211601_P01_WALL-CAVITY-FILL-BACK-LOWER-B1_CAD (Autodesk Fusion 360 design; units mm, degrees)
description: WALL - CAVITY FILL - BACK LOWER - B1 | Vách hậu - bông PET dưới trái | P01 | position B1
part number: 211601
description: WALL - CAVITY FILL - BACK LOWER - B1 | Vách hậu - bông PET dưới trái | P01
Autodesk Fusion 360 part; units mm, degrees
ref_plane "WorkPlane1" through (0, 0, 132.26) normal (0, 0, 1) x (1, 0, 0) in component "211601 WALL - CAVITY FILL - BACK LOWER - B1"
sketch "SKETCH - FILL BAY 1" plane through (0, 0, 132.26) normal (0, 0, 1) x (1, 0, 0) in component "211601 WALL - CAVITY FILL - BACK LOWER - B1"
  line L0 (-1181.74, 804) -> (-808.7433, 804)
  line L1 (-808.7433, 804) -> (-808.7433, 844)
  line L2 (-808.7433, 844) -> (-1181.74, 844)
  line L3 (-1181.74, 844) -> (-1181.74, 804)
  dimension "d162" = 372.9967
  dimension "d163" = 40
  dimension "d164" = 1181.74
  dimension "d165" = 804
  constraint horizontal L0
  constraint vertical L1
  constraint horizontal L2
  constraint vertical L3
  measures "d162" horizontal distance of L0.start L0.end
  measures "d163" vertical distance of L0.start L2.end
  measures "d164" horizontal distance of origin L0.start
  measures "d165" vertical distance of origin L0.start
extrude "EXTRUDE - FILL BAY 1" add sketch "SKETCH - FILL BAY 1" along normal blind 1078.61 makes body 1 in component "211601 WALL - CAVITY FILL - BACK LOWER - B1"
pattern_linear "PATTERN - FILL BAYS" count 3 spacing 392.9967 along (1, 0, 0) of bodies 1 makes body 2 at (-540.0789, 844, 851.3333) makes body 3 at (-147.0822, 844, 491.7967) in component "211601 WALL - CAVITY FILL - BACK LOWER - B1"
ref_plane "WorkPlane2" through (0, 0, 132.26) normal (0, 0, 1) x (1, 0, 0) in component "211601 WALL - CAVITY FILL - BACK LOWER - B1"
sketch "SKETCH - FILL POCKET BOTTOM BOLT 1" plane through (0, 0, 132.26) normal (0, 0, 1) x (1, 0, 0) in component "211601 WALL - CAVITY FILL - BACK LOWER - B1"
  line L0 (-1011.74, 804) -> (-951.74, 804)
  line L1 (-951.74, 804) -> (-951.74, 844)
  line L2 (-951.74, 844) -> (-1011.74, 844)
  line L3 (-1011.74, 844) -> (-1011.74, 804)
  dimension "d174" = 60
  dimension "d175" = 40
  dimension "d176" = 1011.74
  dimension "d177" = 804
  constraint horizontal L0
  constraint vertical L1
  constraint horizontal L2
  constraint vertical L3
  measures "d174" horizontal distance of L0.start L0.end
  measures "d175" vertical distance of L0.start L2.end
  measures "d176" horizontal distance of origin L0.start
  measures "d177" vertical distance of origin L0.start
extrude "CUT - FILL POCKET BOTTOM BOLT 1" cut sketch "SKETCH - FILL POCKET BOTTOM BOLT 1" along normal blind 60 bodies 1 in component "211601 WALL - CAVITY FILL - BACK LOWER - B1"
ref_plane "WorkPlane3" through (0, 0, 132.26) normal (0, 0, 1) x (1, 0, 0) in component "211601 WALL - CAVITY FILL - BACK LOWER - B1"
sketch "SKETCH - FILL POCKET BOTTOM BOLT 2" plane through (0, 0, 132.26) normal (0, 0, 1) x (1, 0, 0) in component "211601 WALL - CAVITY FILL - BACK LOWER - B1"
  line L0 (-758.7433, 804) -> (-698.7433, 804)
  line L1 (-698.7433, 804) -> (-698.7433, 844)
  line L2 (-698.7433, 844) -> (-758.7433, 844)
  line L3 (-758.7433, 844) -> (-758.7433, 804)
  dimension "d182" = 60
  dimension "d183" = 40
  dimension "d184" = 758.7433
  dimension "d185" = 804
  constraint horizontal L0
  constraint vertical L1
  constraint horizontal L2
  constraint vertical L3
  measures "d182" horizontal distance of L0.start L0.end
  measures "d183" vertical distance of L0.start L2.end
  measures "d184" horizontal distance of origin L0.start
  measures "d185" vertical distance of origin L0.start
extrude "CUT - FILL POCKET BOTTOM BOLT 2" cut sketch "SKETCH - FILL POCKET BOTTOM BOLT 2" along normal blind 60 bodies 2 in component "211601 WALL - CAVITY FILL - BACK LOWER - B1"
ref_plane "WorkPlane4" through (0, 0, 132.26) normal (0, 0, 1) x (1, 0, 0) in component "211601 WALL - CAVITY FILL - BACK LOWER - B1"
sketch "SKETCH - FILL POCKET BOTTOM BOLT 3" plane through (0, 0, 132.26) normal (0, 0, 1) x (1, 0, 0) in component "211601 WALL - CAVITY FILL - BACK LOWER - B1"
  line L0 (-505.7467, 804) -> (-445.7467, 804)
  line L1 (-445.7467, 804) -> (-445.7467, 844)
  line L2 (-445.7467, 844) -> (-505.7467, 844)
  line L3 (-505.7467, 844) -> (-505.7467, 804)
  dimension "d190" = 60
  dimension "d191" = 40
  dimension "d192" = 505.7467
  dimension "d193" = 804
  constraint horizontal L0
  constraint vertical L1
  constraint horizontal L2
  constraint vertical L3
  measures "d190" horizontal distance of L0.start L0.end
  measures "d191" vertical distance of L0.start L2.end
  measures "d192" horizontal distance of origin L0.start
  measures "d193" vertical distance of origin L0.start
extrude "CUT - FILL POCKET BOTTOM BOLT 3" cut sketch "SKETCH - FILL POCKET BOTTOM BOLT 3" along normal blind 60 bodies 2 in component "211601 WALL - CAVITY FILL - BACK LOWER - B1"
ref_plane "WorkPlane5" through (0, 0, 132.26) normal (0, 0, 1) x (1, 0, 0) in component "211601 WALL - CAVITY FILL - BACK LOWER - B1"
sketch "SKETCH - FILL POCKET BOTTOM BOLT 4" plane through (0, 0, 132.26) normal (0, 0, 1) x (1, 0, 0) in component "211601 WALL - CAVITY FILL - BACK LOWER - B1"
  line L0 (-252.75, 804) -> (-192.75, 804)
  line L1 (-192.75, 804) -> (-192.75, 844)
  line L2 (-192.75, 844) -> (-252.75, 844)
  line L3 (-252.75, 844) -> (-252.75, 804)
  dimension "d198" = 60
  dimension "d199" = 40
  dimension "d200" = 252.75
  dimension "d201" = 804
  constraint horizontal L0
  constraint vertical L1
  constraint horizontal L2
  constraint vertical L3
  measures "d198" horizontal distance of L0.start L0.end
  measures "d199" vertical distance of L0.start L2.end
  measures "d200" horizontal distance of origin L0.start
  measures "d201" vertical distance of origin L0.start
extrude "CUT - FILL POCKET BOTTOM BOLT 4" cut sketch "SKETCH - FILL POCKET BOTTOM BOLT 4" along normal blind 60 bodies 3 in component "211601 WALL - CAVITY FILL - BACK LOWER - B1"
ref_plane "WorkPlane6" through (0, 0, 302.26) normal (0, 0, 1) x (1, 0, 0) in component "211601 WALL - CAVITY FILL - BACK LOWER - B1"
sketch "SKETCH - FILL POCKET CORNER BOLT 1" plane through (0, 0, 302.26) normal (0, 0, 1) x (1, 0, 0) in component "211601 WALL - CAVITY FILL - BACK LOWER - B1"
  line L0 (-1181.74, 804) -> (-1121.74, 804)
  line L1 (-1121.74, 804) -> (-1121.74, 844)
  line L2 (-1121.74, 844) -> (-1181.74, 844)
  line L3 (-1181.74, 844) -> (-1181.74, 804)
  dimension "d206" = 60
  dimension "d207" = 40
  dimension "d208" = 1181.74
  dimension "d209" = 804
  constraint horizontal L0
  constraint vertical L1
  constraint horizontal L2
  constraint vertical L3
  measures "d206" horizontal distance of L0.start L0.end
  measures "d207" vertical distance of L0.start L2.end
  measures "d208" horizontal distance of origin L0.start
  measures "d209" vertical distance of origin L0.start
extrude "CUT - FILL POCKET CORNER BOLT 1" cut sketch "SKETCH - FILL POCKET CORNER BOLT 1" along normal blind 60 bodies 1 in component "211601 WALL - CAVITY FILL - BACK LOWER - B1"
ref_plane "WorkPlane7" through (0, 0, 641.565) normal (0, 0, 1) x (1, 0, 0) in component "211601 WALL - CAVITY FILL - BACK LOWER - B1"
sketch "SKETCH - FILL POCKET CORNER BOLT 2" plane through (0, 0, 641.565) normal (0, 0, 1) x (1, 0, 0) in component "211601 WALL - CAVITY FILL - BACK LOWER - B1"
  line L0 (-1181.74, 804) -> (-1121.74, 804)
  line L1 (-1121.74, 804) -> (-1121.74, 844)
  line L2 (-1121.74, 844) -> (-1181.74, 844)
  line L3 (-1181.74, 844) -> (-1181.74, 804)
  dimension "d214" = 60
  dimension "d215" = 40
  dimension "d216" = 1181.74
  dimension "d217" = 804
  constraint horizontal L0
  constraint vertical L1
  constraint horizontal L2
  constraint vertical L3
  measures "d214" horizontal distance of L0.start L0.end
  measures "d215" vertical distance of L0.start L2.end
  measures "d216" horizontal distance of origin L0.start
  measures "d217" vertical distance of origin L0.start
extrude "CUT - FILL POCKET CORNER BOLT 2" cut sketch "SKETCH - FILL POCKET CORNER BOLT 2" along normal blind 60 bodies 1 in component "211601 WALL - CAVITY FILL - BACK LOWER - B1"
ref_plane "WorkPlane8" through (0, 0, 980.87) normal (0, 0, 1) x (1, 0, 0) in component "211601 WALL - CAVITY FILL - BACK LOWER - B1"
sketch "SKETCH - FILL POCKET CORNER BOLT 3" plane through (0, 0, 980.87) normal (0, 0, 1) x (1, 0, 0) in component "211601 WALL - CAVITY FILL - BACK LOWER - B1"
  line L0 (-1181.74, 804) -> (-1121.74, 804)
  line L1 (-1121.74, 804) -> (-1121.74, 844)
  line L2 (-1121.74, 844) -> (-1181.74, 844)
  line L3 (-1181.74, 844) -> (-1181.74, 804)
  dimension "d222" = 60
  dimension "d223" = 40
  dimension "d224" = 1181.74
  dimension "d225" = 804
  constraint horizontal L0
  constraint vertical L1
  constraint horizontal L2
  constraint vertical L3
  measures "d222" horizontal distance of L0.start L0.end
  measures "d223" vertical distance of L0.start L2.end
  measures "d224" horizontal distance of origin L0.start
  measures "d225" vertical distance of origin L0.start
extrude "CUT - FILL POCKET CORNER BOLT 3" cut sketch "SKETCH - FILL POCKET CORNER BOLT 3" along normal blind 60 bodies 1 in component "211601 WALL - CAVITY FILL - BACK LOWER - B1"
component "211601 WALL - CAVITY FILL - BACK LOWER - B1" placed x (1, 0, 0) y (0, 1, 0) z (0, 0, 1) at (0, 0, 0)
equation "pod_w_Ref = 2500 mm" comment "DECIDED: D-01; conventions s4 (X = +-1250)"
equation "pod_d_Ref = 1700 mm" comment "DECIDED: D-01; conventions s4 (Y = +-850)"
equation "pod_h_Ref = 2400 mm" comment "DECIDED: D-21 (room floor to roof skin top)"
equation "glide_h_Ref = 10 mm" comment "ASSUMPTION: layout study inputs.py glide_h"
equation "band_h_Ref = 100 mm" comment "SOURCE: layout study B1 list B-BAND 100x40; inputs.py base_h"
equation "outer_t_Ref = skin_t_Ref + bond_t_Ref + frame_t_Ref" comment "DECIDED: PM ruling 2026-10-31: ACP 3 + bond line 3 + frame 40, walls and ceiling (was 43)"
equation "cav_gap_Ref = 4 mm" comment "DECIDED: D-16, D-42: the gap between the outer panel and the lining cassette in the wall and ceiling stack"
equation "cass_t_Ref = 34 mm" comment "SOURCE: layout study B1 final list L-CASS 34 (tray + 25 gap + felt 9)"
equation "stack_t_Ref = outer_t_Ref + cav_gap_Ref + cass_t_Ref" comment "CALCULATION: D-16, D-42 stack, walls and ceiling: outer panel + cavity gap + cassette (PM ruling 2026-10-31 on outer_t)"
equation "lin_gap_Ref = 4 mm" comment "ASSUMPTION: PM ruling pass C: gap above the upper side linings so they stay floating (= the 4 mm stack gap)"
equation "seam_gap_Ref = 2.26 mm" comment "DECIDED: PM ruling 2026-10-31 (Mechanical Checker F-001, F-005): the Joints Engineer's 2.26 mm at all nine site seam types, set by a metal stop (1.5 stop washer + 0.76 rivnut head; joints register section 2.8)"
equation "wall_z0_Ref = glide_h_Ref + band_h_Ref" comment "CALCULATION: base band top: glides + band"
equation "panel_z0_Ref = wall_z0_Ref + seam_gap_Ref" comment "CALCULATION: walls stand one seam_gap above the band top (joints register 2.8, IF-01)"
equation "back_oh_Ref = pod_h_Ref - outer_t_Ref - seam_gap_Ref - panel_z0_Ref" comment "CALCULATION: PM ruling 2026-10-31 (pass D, F-004): the back outer frames run up to the ceiling frame (pod_h - outer_t), less the seam_gap under it, closing the slot at the back top edge"
equation "back_ph_Ref = ( back_oh_Ref - seam_gap_Ref ) / 2" comment "CALCULATION: D-23: 4 sheets on the back, two equal rows with one seam_gap between them (joints register 2.8); the lower back linings match the lower row, as on the side walls"
equation "half_pw_Ref = ( pod_w_Ref - 2 * outer_t_Ref - 3 * seam_gap_Ref ) / 2" comment "CALCULATION: SKIN width of each back and ceiling panel: two skins and three seam_gap seams between the side frames (F-001, joints register 2.8)"
equation "n_base_bolt_Ref = 4" comment "DECIDED: PM ruling 2026-10-31, J-BASE-01: bolts per panel along the band, evenly spaced"
equation "skin_t_Ref = 3 mm" comment "DECIDED: ACP skin, walls and ceiling (D-16; PM ruling 2026-10-31 on outer_t)"
equation "bond_t_Ref = 3 mm" comment "DECIDED: bond line between the ACP and the frame (PM ruling 2026-10-31 on outer_t)"
equation "frame_t_Ref = 40 mm" comment "DECIDED: aluminium frame tube depth, walls and ceiling (PM ruling 2026-10-31 on outer_t)"
equation "close_gap_Ref = 5.5 mm" comment "DECIDED: PM ruling 2026-10-31 (joints register, F-011/F-012): frame gap at the closing seams B1-B2, B3-B4 and C1-C2, which have no hard stop (slotted holes, thicker gasket)"
equation "half_fw_Ref = ( pod_w_Ref - 2 * outer_t_Ref - 2 * seam_gap_Ref - close_gap_Ref ) / 2" comment "CALCULATION: FRAME width of each back and ceiling panel: the skins overhang their frames by half_pw - half_fw at the closing seam (PM ruling 2026-10-31)"
equation "bolt_edge_inset_Ref = 220 mm" comment "DECIDED: PM ruling 2026-10-31: on every bolted edge the end bolts sit this far in from each panel end (the FRAME end, where the bolts go), the rest evenly spaced"
equation "spigot_inset_Ref = 100 mm" comment "DECIDED: PM ruling 2026-10-31: locating spigots this far in from each panel end (round hole at one end, slot at the other)"
equation "pod_w = pod_w_Ref" comment "LINKED: pod_w_Ref, derived from 100000_P04_POD-SKELETON_CAD v4 (skeleton is the single source)"
equation "pod_d = pod_d_Ref" comment "LINKED: pod_d_Ref, derived from 100000_P04_POD-SKELETON_CAD v4 (skeleton is the single source)"
equation "pod_h = pod_h_Ref" comment "LINKED: pod_h_Ref, derived from 100000_P04_POD-SKELETON_CAD v4 (skeleton is the single source)"
equation "panel_z0 = panel_z0_Ref" comment "LINKED: panel_z0_Ref, derived from 100000_P04_POD-SKELETON_CAD v4 (skeleton is the single source)"
equation "back_ph = back_ph_Ref" comment "LINKED: back_ph_Ref, derived from 100000_P04_POD-SKELETON_CAD v4 (skeleton is the single source)"
equation "back_oh = back_oh_Ref" comment "LINKED: back_oh_Ref, derived from 100000_P04_POD-SKELETON_CAD v4 (skeleton is the single source)"
equation "half_pw = half_pw_Ref" comment "LINKED: half_pw_Ref, derived from 100000_P04_POD-SKELETON_CAD v4 (skeleton is the single source)"
equation "half_fw = half_fw_Ref" comment "LINKED: half_fw_Ref, derived from 100000_P04_POD-SKELETON_CAD v4 (skeleton is the single source)"
equation "close_gap = close_gap_Ref" comment "LINKED: close_gap_Ref, derived from 100000_P04_POD-SKELETON_CAD v4 (skeleton is the single source)"
equation "stack_t = stack_t_Ref" comment "LINKED: stack_t_Ref, derived from 100000_P04_POD-SKELETON_CAD v4 (skeleton is the single source)"
equation "outer_t = outer_t_Ref" comment "LINKED: outer_t_Ref, derived from 100000_P04_POD-SKELETON_CAD v4 (skeleton is the single source)"
equation "cass_t = cass_t_Ref" comment "LINKED: cass_t_Ref, derived from 100000_P04_POD-SKELETON_CAD v4 (skeleton is the single source)"
equation "lin_gap = lin_gap_Ref" comment "LINKED: lin_gap_Ref, derived from 100000_P04_POD-SKELETON_CAD v4 (skeleton is the single source)"
equation "seam_gap = seam_gap_Ref" comment "LINKED: seam_gap_Ref, derived from 100000_P04_POD-SKELETON_CAD v4 (skeleton is the single source)"
equation "skin_t = skin_t_Ref" comment "LINKED: skin_t_Ref, derived from 100000_P04_POD-SKELETON_CAD v4 (skeleton is the single source)"
equation "bond_t = bond_t_Ref" comment "LINKED: bond_t_Ref, derived from 100000_P04_POD-SKELETON_CAD v4 (skeleton is the single source)"
equation "bolt_edge_inset = bolt_edge_inset_Ref" comment "LINKED: bolt_edge_inset_Ref, derived from 100000_P04_POD-SKELETON_CAD v4 (skeleton is the single source)"
equation "spigot_inset = spigot_inset_Ref" comment "LINKED: spigot_inset_Ref, derived from 100000_P04_POD-SKELETON_CAD v4 (skeleton is the single source)"
equation "n_base_bolt = n_base_bolt_Ref" comment "LINKED: n_base_bolt_Ref, derived from 100000_P04_POD-SKELETON_CAD v4 (skeleton is the single source)"
equation "tube_w = 20 mm" comment "CONFIRMED: D-34, D-54: aluminium tube 20 x 40 x 1.2; the 20 mm face carries the skin, so the 40 mm runs through the wall (outer_t = ACP 3 + frame 40). The joint register may turn it for the bond width (HOLD)"
equation "tube_d = outer_t - skin_t - bond_t" comment "CALCULATION: frame depth = outer panel 46 - skin 3 - bond 3 = 40 (D-34)"
equation "tube_t = 1.2 mm" comment "CONFIRMED: D-34, D-54, D-85: perimeter members (rails, front and back stiles) keep the 1.2 mm wall; they carry the rivnuts (grip check passed)"
equation "stud_t = 1.0 mm" comment "CONFIRMED: D-85 (weight): intermediate studs at a 1.0 mm wall; they carry no rivnut, only the skin's bond line"
equation "stile_pitch_max = 400 mm" comment "CONFIRMED: D-16, D-34: members 400 mm apart or less, to keep the ACP flat"
equation "skin_setback = 0 mm" comment "ASSUMPTION: skin edge set back from the frame's top and bottom edges: 0, so the outside reveal equals the 2.26 seam gap (D-23: crisp, aligned reveals; joints register 2.8 leaves the setback to the WALL drawing)"
equation "fill_t = tube_d" comment "CALCULATION: 40 mm PET fill fills the frame depth (D-34; layout study 40 mm)"
equation "bolt_d = 7 mm" comment "CONFIRMED: PM ruling on F-009: bolt holes 7.0 (0.51 float), position tolerance 0.4 (+-0.2) from the spigot hole, CNC or drill jig (joints register FR-02)"
equation "access_d = 19 mm" comment "CALCULATION: register FR-03: passes the 18 mm head washer (ISO 7093-1, R-J10), the M6 head and the 5 mm key; holds the grommet retainer (H-02)"
equation "bolt_line_y = pod_d / 2 - skin_t - bond_t - tube_d / 2" comment "CONFIRMED: J-WALL-02 bolt line on the back panel's tube centre, Y 824 (joints register R-J15, FR-07)"
equation "rivnut_d = 9.53 mm" comment "SOURCE: Sherex CAH3-610-4.2 hole 9.53 +0.10 (HW-SEL A5; register H-03)"
equation "spigot_d = 8.5 mm" comment "ASSUMPTION: register FR-05: hole for the 8 mm locating spigot H-05"
equation "spigot_slot = 14 mm" comment "ASSUMPTION: register FR-05: slot length for the second spigot"
equation "spigot_edge = spigot_inset" comment "CALCULATION: the skeleton's spigot_inset: spigots 100 from each end of the edge (PM ruling 2026-10-31, R-J13)"
equation "bolt_edge = bolt_edge_inset" comment "CALCULATION: the skeleton's bolt_edge_inset: end bolts 220 in from the panel's ends, evenly spaced, every bolt 30 or more from any stile (PM ruling 2026-10-31, R-J14)"
equation "pocket_w = 60 mm" comment "ASSUMPTION: register FR-10: fill left out 60 x 60 next to each bolt for the key"
equation "felt_t = 9 mm" comment "SOURCE: plan VT03-PET 9 mm PET felt; HW-SEL A3; D-31 (the factory's felt)"
equation "tray_t = 0.5 mm" comment "CONFIRMED: D-37: galvanised steel tray 0.5 mm"
equation "tray_h = cass_t" comment "CONFIRMED: PM ruling 2026-10-31 (WALL group, option 1): the wall cassettes use the ceiling's tray, returns the full cassette depth (34) turned in as lips that hold the felt, no ribs; settles H09 for the walls"
equation "lip_w = 12 mm" comment "CONFIRMED: PM ruling 2026-10-31 (WALL group, option 1): 12 mm lips hold the felt edge"
equation "bend_r = tray_t" comment "ASSUMPTION: inside bend radius 1 x t for 0.5 mm DX51D (the sheet metal rule's bend radius is its Thickness); the factory's tooling sets it (guideline 9)"
equation "felt_c = 1 mm" comment "ASSUMPTION: felt edge clearance inside the returns, as the ceiling cassette"
equation "gap_h = tray_h - felt_t - 2 * tray_t" comment "CALCULATION: air gap between the tray base and the felt (24): the acoustic gap (D-17) and the cable path (D-26)"
equation "clip_zone_h = 60 mm" comment "ASSUMPTION: height of each reserved clip zone (H03: no clip named)"
equation "clip_zone_dz = 100 mm" comment "ASSUMPTION: clip zone centre from the cassette's top and bottom edges (H03)"
equation "stopw_od = 20 mm" comment "SOURCE: joints register H-08: stop washer Ø10.5 x Ø20 x 1.5 (PROPOSED part)"
equation "stopw_id = 10.5 mm" comment "SOURCE: joints register H-08"
equation "stopw_t = 1.5 mm" comment "SOURCE: joints register H-08: rivnut head 0.76 + washer 1.5 = the 2.26 stop (R-J5)"
equation "rivnut_head_d = 12.96 mm" comment "SOURCE: Sherex CAH3-610-4.2 head Ø12.96 (joints register H-03, SHX)"
equation "rivnut_head_t = 0.76 mm" comment "SOURCE: Sherex CAH3-610-4.2 head 0.76 ±0.08 (H-03, SHX)"
equation "rivnut_body_d = 9.5 mm" comment "SOURCE: Sherex CAH3-610-4.2 body Ø9.50 max (H-03, SHX)"
equation "rivnut_len = 10.16 mm" comment "SOURCE: Sherex CAH3-610-4.2 installed length 10.16 max under the head (H-03, SHX); the bulge inside the tube is not modelled"
equation "m6_d = 6 mm" comment "CALCULATION: M6 threads shown at their 6 mm major diameter (no modelled thread)"
equation "spigot_pin_d = 8 mm" comment "SOURCE: joints register H-05: Ø8 stainless pin (PROPOSED, assumption sizes)"
equation "spigot_proud = 8 mm" comment "SOURCE: joints register H-05: stands 8 proud (read as: of the joint face)"
equation "spigot_thread_l = 10 mm" comment "ASSUMPTION: M6 thread into the spigot rivnut; H-05 gives no length; 10 stays inside the rivnut's 10.16"
equation "lead_in = 1 mm" comment "SOURCE: joints register 2.10 (R-J9): 1 x 45 degree lead-in on the top edge of each closing-seam face, so the panel beside it drops in past it without catching the bulb seal"
equation "pnl_len = half_pw" comment "CALCULATION: skeleton half_pw: the back panel's skin width (1200.61 on P04)"
equation "frm_len = half_fw" comment "CALCULATION: the skeleton's half_fw, 1198.99: the frame stops close_gap / 2 from X 0 and 1.62 short of its skin (R-J16)"
equation "pnl_h = back_ph" comment "CALCULATION: skeleton back row height (1118.61 on P04)"
equation "frm_h = pnl_h" comment "CALCULATION: the frame fills the row height; the seam gaps are outside it (P04)"
equation "top_h = tube_w" comment "CALCULATION: the back panels' top rails stay 20 x 40 (the ceiling's back member is the 40 x 40, R-J3)"
equation "stile_n_mid = ceil(( frm_len - tube_w ) / stile_pitch_max) - 1" comment "CALCULATION: intermediate stiles so that no stile pitch exceeds stile_pitch_max"
equation "stile_pitch = ( frm_len - tube_w ) / ( stile_n_mid + 1 )" comment "CALCULATION: equal stile pitch, centre to centre"
equation "stile_len = frm_h - 2 * tube_w" comment "CALCULATION: stiles between the full-width rails (butt joints)"
equation "n_len_bolt = n_base_bolt" comment "CALCULATION: the skeleton's n_base_bolt (4): also on the horizontal seam and the ceiling back edge (register 2.9; the skeleton's n_ceil_back_bolt 3 is an old assumption, flagged)"
equation "len_bolt_pitch = ( frm_len - 2 * bolt_edge ) / ( n_len_bolt - 1 )" comment "CALCULATION: 253.00 on P04: 220, 473.00, 725.99, 978.99 from the frame's ends (register 2.9; the skeleton's back_base_pitch uses the 1200.61 skin and gives 253.54, flagged to its owner)"
equation "n_side_jnt = 3" comment "SOURCE: 3 bolts on the back corner and on the closing seam (register 2.9)"
equation "side_jnt_pitch = ( pnl_h - 2 * bolt_edge ) / ( n_side_jnt - 1 )" comment "CALCULATION: 339.31 on P04: 220, 559.31, 898.61 up the 1118.61 edge (register 2.9)"
equation "cass_len = pod_w / 2 - stack_t - seam_gap / 2" comment "ASSUMPTION: PROPOSED (WALL): from the side lining's face to seam_gap / 2 short of X 0. Each cassette hangs on its own panel's frame and the closing seam moves (5.2 to 5.8, register 2.11), so the skeleton's touching edges at X 0 could clash; a 2.26 gap matches the skin seam above it (R-J16) and takes the H-14 edge seal"
equation "cass_h = pnl_h" comment "CALCULATION: lower: the row height; upper: up to lin_gap under the ceiling frame, floating (D-57; P04)"
equation "d160 = ( panel_z0 ) + tube_w"
equation "d162 = ( ( -close_gap / 2 - half_fw ) + stile_pitch ) - ( ( -close_gap / 2 - half_fw ) + tube_w )"
equation "d163 = ( pod_d / 2 - skin_t - bond_t ) - ( pod_d / 2 - outer_t )"
equation "d164 = abs(( -close_gap / 2 - half_fw ) + tube_w)"
equation "d165 = abs(pod_d / 2 - outer_t)"
equation "d166 = ( ( panel_z0 + back_ph ) - top_h ) - ( ( panel_z0 ) + tube_w )"
equation "d168 = stile_n_mid + 1"
equation "d170 = stile_pitch"
equation "d172 = ( panel_z0 ) + tube_w"
equation "d174 = ( ( ( -close_gap / 2 - half_fw ) + bolt_edge + 0 * len_bolt_pitch ) + pocket_w / 2 ) - ( ( ( -close_gap / 2 - half_fw ) + bolt_edge + 0 * len_bolt_pitch ) - pocket_w / 2 )"
equation "d175 = ( pod_d / 2 - skin_t - bond_t ) - ( pod_d / 2 - outer_t )"
equation "d176 = abs(( ( -close_gap / 2 - half_fw ) + bolt_edge + 0 * len_bolt_pitch ) - pocket_w / 2)"
equation "d177 = abs(pod_d / 2 - outer_t)"
equation "d178 = ( ( ( panel_z0 ) + tube_w ) + pocket_w ) - ( ( panel_z0 ) + tube_w )"
equation "d180 = ( panel_z0 ) + tube_w"
equation "d182 = ( ( ( -close_gap / 2 - half_fw ) + bolt_edge + 1 * len_bolt_pitch ) + pocket_w / 2 ) - ( ( ( -close_gap / 2 - half_fw ) + bolt_edge + 1 * len_bolt_pitch ) - pocket_w / 2 )"
equation "d183 = ( pod_d / 2 - skin_t - bond_t ) - ( pod_d / 2 - outer_t )"
equation "d184 = abs(( ( -close_gap / 2 - half_fw ) + bolt_edge + 1 * len_bolt_pitch ) - pocket_w / 2)"
equation "d185 = abs(pod_d / 2 - outer_t)"
equation "d186 = ( ( ( panel_z0 ) + tube_w ) + pocket_w ) - ( ( panel_z0 ) + tube_w )"
equation "d188 = ( panel_z0 ) + tube_w"
equation "d190 = ( ( ( -close_gap / 2 - half_fw ) + bolt_edge + 2 * len_bolt_pitch ) + pocket_w / 2 ) - ( ( ( -close_gap / 2 - half_fw ) + bolt_edge + 2 * len_bolt_pitch ) - pocket_w / 2 )"
equation "d191 = ( pod_d / 2 - skin_t - bond_t ) - ( pod_d / 2 - outer_t )"
equation "d192 = abs(( ( -close_gap / 2 - half_fw ) + bolt_edge + 2 * len_bolt_pitch ) - pocket_w / 2)"
equation "d193 = abs(pod_d / 2 - outer_t)"
equation "d194 = ( ( ( panel_z0 ) + tube_w ) + pocket_w ) - ( ( panel_z0 ) + tube_w )"
equation "d196 = ( panel_z0 ) + tube_w"
equation "d198 = ( ( ( -close_gap / 2 - half_fw ) + bolt_edge + 3 * len_bolt_pitch ) + pocket_w / 2 ) - ( ( ( -close_gap / 2 - half_fw ) + bolt_edge + 3 * len_bolt_pitch ) - pocket_w / 2 )"
equation "d199 = ( pod_d / 2 - skin_t - bond_t ) - ( pod_d / 2 - outer_t )"
equation "d200 = abs(( ( -close_gap / 2 - half_fw ) + bolt_edge + 3 * len_bolt_pitch ) - pocket_w / 2)"
equation "d201 = abs(pod_d / 2 - outer_t)"
equation "d202 = ( ( ( panel_z0 ) + tube_w ) + pocket_w ) - ( ( panel_z0 ) + tube_w )"
equation "d204 = ( ( panel_z0 ) + bolt_edge + 0 * side_jnt_pitch ) - pocket_w / 2"
equation "d206 = ( ( ( -close_gap / 2 - half_fw ) + 1 * tube_w ) + pocket_w ) - ( ( -close_gap / 2 - half_fw ) + 1 * tube_w )"
equation "d207 = ( pod_d / 2 - skin_t - bond_t ) - ( pod_d / 2 - outer_t )"
equation "d208 = abs(( -close_gap / 2 - half_fw ) + 1 * tube_w)"
equation "d209 = abs(pod_d / 2 - outer_t)"
equation "d210 = ( ( ( panel_z0 ) + bolt_edge + 0 * side_jnt_pitch ) + pocket_w / 2 ) - ( ( ( panel_z0 ) + bolt_edge + 0 * side_jnt_pitch ) - pocket_w / 2 )"
equation "d212 = ( ( panel_z0 ) + bolt_edge + 1 * side_jnt_pitch ) - pocket_w / 2"
equation "d214 = ( ( ( -close_gap / 2 - half_fw ) + 1 * tube_w ) + pocket_w ) - ( ( -close_gap / 2 - half_fw ) + 1 * tube_w )"
equation "d215 = ( pod_d / 2 - skin_t - bond_t ) - ( pod_d / 2 - outer_t )"
equation "d216 = abs(( -close_gap / 2 - half_fw ) + 1 * tube_w)"
equation "d217 = abs(pod_d / 2 - outer_t)"
equation "d218 = ( ( ( panel_z0 ) + bolt_edge + 1 * side_jnt_pitch ) + pocket_w / 2 ) - ( ( ( panel_z0 ) + bolt_edge + 1 * side_jnt_pitch ) - pocket_w / 2 )"
equation "d220 = ( ( panel_z0 ) + bolt_edge + 2 * side_jnt_pitch ) - pocket_w / 2"
equation "d222 = ( ( ( -close_gap / 2 - half_fw ) + 1 * tube_w ) + pocket_w ) - ( ( -close_gap / 2 - half_fw ) + 1 * tube_w )"
equation "d223 = ( pod_d / 2 - skin_t - bond_t ) - ( pod_d / 2 - outer_t )"
equation "d224 = abs(( -close_gap / 2 - half_fw ) + 1 * tube_w)"
equation "d225 = abs(pod_d / 2 - outer_t)"
equation "d226 = ( ( ( panel_z0 ) + bolt_edge + 2 * side_jnt_pitch ) + pocket_w / 2 ) - ( ( ( panel_z0 ) + bolt_edge + 2 * side_jnt_pitch ) - pocket_w / 2 )"
named bodies: "FILL - BAY 1", "FILL - BAY 2", "FILL - BAY 3"
